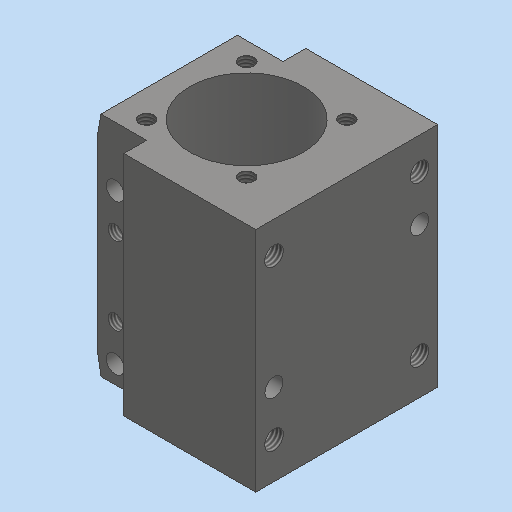
# Autodesk Inventor part: MM0948AN120_G01_105
Saved by Autodesk Inventor 2023.3 (Build 273359000, 359)
## iProperties
RuleStatus: InUse
Created: 2023-03-23
Part Number: MM0948AN120_G01_105
Material: 1.2379 X155CrVMo12-1
Description: =<RBPARTNOTITLE2>
Document SubType Name: Modeling
Designer: ric7an
Mass: 407.723 g
Surface Area: 162.871 cm^2
Volume: 51.9392 cm^3
Density: 7.85 g/cm^3
Appearance: Stahl - rostfrei AnP
AnP_Kategorie: 1
AnP_Material: =<Material>
MaxAbmaße: 50 x 40 x 39,9 (FM)
AnP_TemplVers: 20200821
RBDOCUMENTTYPE: DRF
RBDOCUMENTVERSION: 00
RBDRAWINGMAINSCALE: 1:1
RBDRAWINGMISSINGSPEC: --
RBDRAWINGVOLUME: --
RBDSV1: 0850
RBGBEDGESIN1: +0,5
RBGBEDGESIN2: +0,2
RBGBEDGESOUT1: -0,3
RBGBEDGESOUT2: -0,1
RBMATERIAL: =<Material>
RBMATMEETS: --
RBMATNO: =<Part Number>
RBPARTMADEOF: 50 x 40 x 39,9 (FM)
RBPARTNO: SIEHE MNR
RBPARTNOTITLE1: manufactured part
RBPARTNOTITLE2: Anfertigungsteil
RBPARTSAFETYINDICATOR: --
RBSURFACE: plasma nitrided 1000 HV, Nht 0,1 + 0,1
RBSURFACE2: plasmanitriert 1000 HV, Nht 0,1 + 0,1
RBZEDGESNORM: ISO13715:2002-06
RBZGENDIMCLASS: m
RBZGENDIMNORM: ISO 2768-1:1989-11
RBZGENGEOCLASS: H
RBZGENGEONORM: ISO 2768-2:1989-11
RBZSURFACENORM: ISO13D2:2002-02
RBZTOLERANCENORM: ISO 14405-1:2010-12
AnP_Kommentar_aktuell: =<Comments>
AnP_Material_aktuell: =<Material>
Author: FH/Wi
Keywords: =<RBPARTMADEOF>
Comments: =<RBSURFACE2>
Revision Number: 01
Autodesk Inventor part; units mm, degrees
ref_plane "YZ Plane" through (0, 0, 0) normal (1, 0, 0) x (0, 1, 0)
ref_plane "XZ Plane" through (0, 0, 0) normal (0, 1, 0) x (-1, 0, 0)
ref_plane "XY Plane" through (0, 0, 0) normal (0, 0, 1) x (1, 0, 0)
sketch "Skizze1" plane through (0, 0, 0) normal (0, 0, 1) x (1, 0, 0)
  line L0 (-7, 20) -> (22, 20)
  line L1 (22, 20) -> (22, -20)
  line L2 (22, -20) -> (-7, -20)
  line L3 (0, 28) -> (0, -28) projected
  line L4 (-36.8, 0) -> (31.8, 0) projected
  line L5 (-27, 5.5) -> (-23.1, 5.5)
  line L6 (-23.1, 5.5) -> (-23.1, 11)
  line L7 (-23.1, 11) -> (-17.9, 11)
  line L8 (-17.9, 11) -> (-17.9, -11)
  line L9 (-17.9, -11) -> (-23.1, -11)
  line L10 (-23.1, -11) -> (-23.1, -5.5)
  line L11 (-23.1, -5.5) -> (-27, -5.5)
  line L12 (-27, -15) -> (-27, -5.5)
  line L13 (-27, 5.5) -> (-27, 15)
  line L14 (-27, 15) -> (-7, 15)
  line L15 (-7, 15) -> (-7, 20)
  line L16 (-27, -15) -> (-7, -15)
  line L17 (-7, -15) -> (-7, -20)
  line L18 (-20.5, 11) -> (-20.5, 8.61)
  line L19 (-17.9, -11) -> (-17.9, -15)
  line L20 (-17.9, 11) -> (-17.9, 15)
  point P0 (0, 0)
  point P1 (-17.9, 0)
  dimension "d79" = 22
  dimension "d84" = 11
  dimension "d85" = 22
  dimension "d87" = 5.2
  dimension "d88" = 27
  dimension "d90" = 30
  dimension "d91" = 40
  dimension "d92" = 49
  dimension "d93" = 6.5
  dimension "d94" = 20
  constraints: 38 end point, 10 perpendicular, 5 point on line, 4 collinear, 4 horizontal, 3 parallel, 2 midpoint, 1 horizontal alignment, 1 vertical, 1 other
  measures "d79" distance from line of L1 point (0, 0)
  measures "d84" distance between parallel lines of L11 L5
  measures "d85" distance of L7.end L8.end
  measures "d87" distance of L6.end L7.end
  measures "d88" distance from line of L13 point (0, 0)
  measures "d90" distance between parallel lines of L16 L14
  measures "d91" distance between parallel lines of L2 L0
  measures "d92" distance between parallel lines of L1 L13
  measures "d93" distance between parallel lines of L18 L13
  measures "d94" distance of L12.start L16.end
extrude "Extrusion1" add sketch "Skizze1" against normal blind 50 contours L0 L3 L4 L8 L20 L14 L15 | L0 L1 L4 L3 | L4 L1 L2 L3 | L3 L2 L17 L16 L19 L8 L4
sketch "Skizze2" plane through (0, 0, 0) normal (0, 0, 1) x (1, 0, 0)
  circle A0 centre (0, 0) radius 12.5
  dimension "d4" = 25
  constraints: 1 centre point, 1 coincident
  measures "d4" diameter of A0
extrude "Extrusion2" cut sketch "Skizze2" against normal blind 39
sketch "Skizze4" plane through (0, 0, 0) normal (0, 0, 1) x (1, 0, 0)
  line L0 (0, 28) -> (0, -28) projected
  line L1 (-25.88, 0) -> (29.98, 0) projected
  point P0 (0, 0)
  point P1 (-11, 11)
  point P2 (-11, -11)
  point P3 (11, -11)
  point P4 (11, 11)
  dimension "d15" = 22
  dimension "d16" = 22
  constraints: 3 symmetric about line
  measures "d15" distance of point (11, 11) point (-11, 11)
  measures "d16" distance of point (-11, -11) point (-11, 11)
hole "Bohrung1" at (-11, 11, 0) at (-11, -11, 0) at (11, -11, 0) at (11, 11, 0) direction (0, 0, -1) diameter 3.242 depth 9 tip angle 118 thread size "M4x0.7" designation "M4" class "6H" standard "ISO Metric profile"
sketch "Skizze5" plane through (0, 0, -50) normal (0, 0, -1) x (-1, 0, 0)
  point P0 (0, 0)
  point P1 (0, 0)
  constraints: 1 coincident
hole "Bohrung2" at (0, 0, -50) direction (0, 0, 1) diameter 10 end through all
chamfer "Fase1" distance 0.5 angle 45 1 edges at (0, -5, -50)
sketch "Skizze6" plane through (22, 27, 0.25) normal (1, 0, 0) x (0, 0, -1)
  line L0 (0.25, -47) -> (0.25, -7) projected
  line L1 (0.25, -27) -> (40, -27)
  line L2 (50.25, -7) -> (50.25, -47) projected
  point P0 (7.25, -11)
  point P1 (42.25, -11)
  point P2 (42.25, -43)
  point P3 (7.25, -43)
  dimension "d35" = 32
  dimension "d37" = 35
  dimension "d77" = 8
  constraints: 2 end point, 2 symmetric about line, 1 horizontal, 1 horizontal alignment, 1 midpoint, 1 vertical alignment
  measures "d35" distance of point (42.25, -43) point (42.25, -11)
  measures "d37" distance of point (42.25, -11) point (7.25, -11)
  measures "d77" distance from line of L2 point (42.25, -11)
hole "Bohrung3" at (22, 16, -7) at (22, 16, -42) at (22, -16, -42) at (22, -16, -7) direction (-1, 0, 0) diameter 4.134 depth 14.2 thread size "M5x0.8" designation "M5" class "6H" standard "ISO Metric profile"
sketch "Skizze9" plane through (22, 27, 0.312) normal (1, 0, 0) x (0, 0, -1)
  circle A0 centre (7.312, -11) radius 2.067 projected
  circle A1 centre (42.312, -43) radius 2.067 projected
  point P0 (17.312, -11)
  point P1 (32.312, -43)
  dimension "d75" = 10
  dimension "d76" = 10
  constraints: 2 horizontal alignment
  measures "d75" distance of A0.centre point (17.312, -11)
  measures "d76" distance of A1.centre point (32.312, -43)
hole "Bohrung6" at (22, 16, -17) at (22, -16, -32) direction (-1, 0, 0) diameter 4 depth 12 tip angle 118
chamfer "Fase2" [suppressed]
sketch "Skizze10" plane through (-17.9, -15, 0) normal (0, -1, 0) x (1, 0, 0)
  line L0 (10.9, 0) -> (10.9, -50) projected
  line L1 (0, 0) -> (10.9, 0) projected
  line L2 (0, 0) -> (0, -50) projected
  line L3 (10.9, -50) -> (0, -50) projected
  point P0 (17.9, 0)
  point P1 (4, -21)
  point P2 (4, -38)
  dimension "d119" = 17
  dimension "d120" = 4
  dimension "d121" = 12
  constraints: 1 vertical alignment
  measures "d119" distance of point (4, -38) point (4, -21)
  measures "d120" distance from line of L2 point (4, -38)
  measures "d121" distance from line of L3 point (4, -38)
hole "Bohrung7" at (-13.9, -15, -21) at (-13.9, -15, -38) direction (0, 1, 0) diameter 3.242 depth 9 tip angle 118 thread size "M4x0.7" designation "M4" class "6H" standard "ISO Metric profile"
chamfer "Fase3" distance 5 angle 10 1 edges at (-17.9, 0, -50) measured on face at (-17.9, 0, -49.5)
chamfer "Fase4" distance 5 angle 10 1 edges at (-17.9, 0, 0) measured on face at (-17.9, 0, -0.5)
sketch "Skizze11" plane through (-17.308, 15, -50) normal (0, 1, 0) x (1, 0, 0)
  circle A0 centre (3.408, -29) radius 1.621 projected
  circle A1 centre (3.408, -12) radius 1.621 projected
  point P0 (3.408, -12)
  point P1 (3.408, -29)
  constraints: 2 coincident
hole "Bohrung8" at (-13.9, 15, -38) at (-13.9, 15, -21) direction (0, -1, 0) diameter 3.242 depth 8 tip angle 118 thread size "M4x0.7" designation "M4" class "6H" standard "ISO Metric profile"
sketch "Skizze12" plane through (-7, 15, 0) normal (0, 1, 0) x (1, 0, 0)
  circle A0 centre (-6.9, 38) radius 1.621 projected
  circle A1 centre (-6.9, 21) radius 1.621 projected
  point P0 (7, 0)
  point P1 (-6.9, 46)
  point P2 (-6.9, 13)
  dimension "d122" = 8
  dimension "d123" = 8
  constraints: 2 vertical alignment
  measures "d122" distance of A0.centre point (-6.9, 46)
  measures "d123" distance of point (-6.9, 13) A1.centre
hole "Bohrung9" at (-13.9, 15, -46) at (-13.9, 15, -13) direction (0, -1, 0) diameter 4 depth 6 tip angle 118
sketch "Skizze13" plane through (-7, -15, -50) normal (0, -1, 0) x (1, 0, 0)
  circle A0 centre (-6.9, 29) radius 1.621 projected
  circle A1 centre (-6.9, 12) radius 1.621 projected
  point P0 (7, 50)
  point P1 (-6.9, 37)
  point P2 (-6.9, 4)
  dimension "d131" = 8
  dimension "d132" = 8
  constraints: 2 vertical alignment
  measures "d131" distance of point (-6.9, 4) A1.centre
  measures "d132" distance of A0.centre point (-6.9, 37)
hole "Bohrung10" at (-13.9, -15, -13) at (-13.9, -15, -46) direction (0, 1, 0) diameter 4 depth 7 tip angle 118
sketch "Skizze14" plane through (0, 0, -39) normal (0, 0, 1) x (1, 0, 0)
  circle A0 centre (0, 0) radius 5 projected
  constraints: 1 coincident
hole "Bohrung11" at (0, 0, -39) direction (0, 0, -1) diameter 12 depth 7
chamfer "Fase5" distance 0.5 angle 45 1 edges at (0, -5, -46)
fillet "Rundung1" radius 5 2 edges at (-17.9, 0, -45) (-17.9, 0, -5)
equation "\"d107\" = d104"
equation "\"d109\" = d106"
equation "\"d104\" = 5"
equation "\"d106\" = 10deg"
